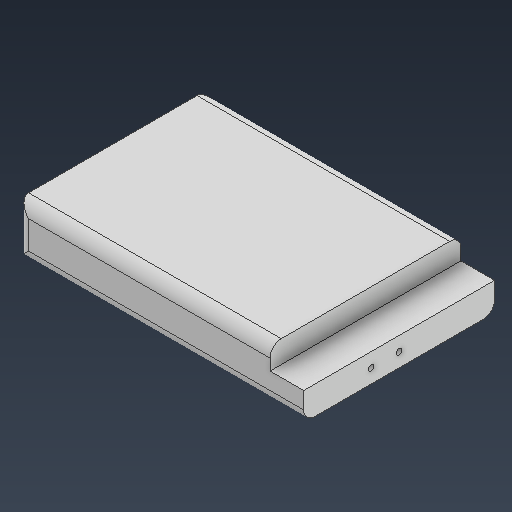
# Autodesk Inventor part: forenkla batteri
Saved by Autodesk Inventor 2027.1 (Build 311270010, 270A)
## iProperties
Created: 2026-09-17
Part Number: forenkla batteri
Material: Generic
Document SubType Name: Modeling
Designer: evenb
Density: 1 g/cm^3
Appearance: Default
Author: evenb
Autodesk Inventor part; units mm, degrees
ref_plane "YZ Plane" through (0, 0, 0) normal (1, 0, 0) x (0, 1, 0)
ref_plane "XZ Plane" through (0, 0, 0) normal (0, 1, 0) x (-1, 0, 0)
ref_plane "XY Plane" through (0, 0, 0) normal (0, 0, 1) x (1, 0, 0)
sketch "Sketch1" plane through (0, 0, 0) normal (0, 1, 0) x (-1, 0, 0)
  line L0 (0, 0) -> (51, 0)
  line L1 (51, 0) -> (51, -34)
  line L2 (51, -34) -> (0, -34)
  line L3 (0, -34) -> (0, 0)
  dimension "d0" = 51
  dimension "d1" = 34
  constraints: 8 end point, 2 parallel, 1 horizontal, 1 perpendicular
  measures "d0" distance of L1.end L2.end
  measures "d1" distance of L0.end L1.end
extrude "Extrusion1" add sketch "Sketch1" along normal blind 9
sketch "Sketch2" plane through (0, 9, 0) normal (0, 1, 0) x (1, 0, 0)
  line L0 (-51, 0) -> (0, 0) projected
  line L1 (0, 0) -> (-6, 0)
  line L2 (-6, 0) -> (-6, 34)
  line L3 (-6, 34) -> (0, 34)
  line L4 (0, 34) -> (0, 0)
  dimension "d4" = 6
  dimension "d5" = 34
  constraints: 8 end point, 2 parallel, 1 horizontal, 1 perpendicular
  measures "d4" distance of L2.end L3.end
  measures "d5" distance of L1.end L2.end
extrude "Extrusion2" cut sketch "Sketch2" against normal blind 4
fillet "Fillet1" radius 2 6 edges at (-28.5, 9, -34) (-28.5, 9, 0) (-25.5, 0, 0) (-25.5, 0, -34) (-51, 4.5, -34) (-51, 4.5, 0)
sketch "Sketch3" plane through (0, 5, 0) normal (1, 0, 0) x (0, 0, -1)
  circle A0 centre (17, -2.5) radius 0.5
  circle A1 centre (12, -2.5) radius 0.5
  line L0 (34, 0) -> (0, 0) projected
  line L1 (0, -3) -> (0, 0) projected
  point P0 (0, -5)
  dimension "d9" = 1
  dimension "d10" = 1
  dimension "d11" = 2.5
  dimension "d12" = 2.5
  dimension "d13" = 17
  dimension "d14" = 12
  constraints: 2 centre point, 2 coincident
  measures "d9" diameter of A1
  measures "d10" diameter of A0
  measures "d11" distance from line of L0 A0.centre
  measures "d12" distance from line of L0 A1.centre
  measures "d13" distance from line of L1 A0.centre
  measures "d14" distance from line of L1 A1.centre
extrude "Extrusion3" cut sketch "Sketch3" against normal blind 1
body "Solid1"
